new-transport (Autodesk Fusion 360 design; units mm, degrees)
Autodesk Fusion 360 part; units mm, degrees
sketch "스케치1" plane through (0, 0, 0) normal (0, 0, 1) x (1, 0, 0)
  line L0 (0, 0) -> (190, 0)
  line L1 (190, 0) -> (190, 190)
  line L2 (190, 190) -> (0, 190)
  line L3 (0, 190) -> (0, 0)
  dimension "d1" = 190
  dimension "d2" = 190
  constraint horizontal L0
  constraint vertical L1
  constraint horizontal L2
  constraint vertical L3
  constraint coincident L0.start L3.end
  measures "d1" distance of L0.start L0.end
  measures "d2" distance of L0.start L2.end
extrude "돌출1" add sketch "스케치1" along normal blind 3 makes body 1 in component "Component"
sketch "스케치2" plane through (0, 0, 3) normal (0, 0, 1) x (-1, 0, 0)
  line L0 (0, -190) -> (0, 0)
  line L1 (0, 0) -> (-190, 0)
  line L2 (-190, 0) -> (-190, -190)
  line L3 (-190, -190) -> (0, -190)
  line L4 (0, 0) -> (-3, 0)
  line L5 (-3, 0) -> (-3, -190)
  line L6 (-3, -190) -> (0, -190)
  line L7 (0, -190) -> (0, 0)
  line L8 (-3, -180) -> (-6, -180)
  line L9 (-6, -180) -> (-6, -170)
  line L10 (-6, -170) -> (-3, -170)
  line L11 (-3, -170) -> (-3, -180)
  line L12 (-3, -10) -> (-6, -10)
  line L13 (-6, -10) -> (-6, -20)
  line L14 (-6, -20) -> (-3, -20)
  line L15 (-3, -20) -> (-3, -10)
  dimension "d5" = 3
  dimension "d6" = 3
  dimension "d7" = 10
  dimension "d8" = 3
  dimension "d9" = 10
  dimension "d10" = 10
  dimension "d11" = 10
  constraint horizontal L4
  constraint vertical L5
  constraint horizontal L6
  constraint vertical L7
  constraint coincident L3 L5.end
  constraint coincident L0.end L1.start
  constraint horizontal L8
  constraint vertical L9
  constraint horizontal L10
  constraint vertical L11
  constraint coincident L5 L8.start
  constraint horizontal L12
  constraint vertical L13
  constraint horizontal L14
  constraint vertical L15
  constraint coincident L5 L12.start
  measures "d5" distance of L5.end L0.start
  measures "d6" distance of L8.start L8.end
  measures "d7" distance of L8.start L10.end
  measures "d8" distance of L12.start L12.end
  measures "d9" distance of L12.start L14.end
  measures "d10" distance of L1 L12
  measures "d11" distance of L3 L8
extrude "돌출1'" add sketch "스케치2" along normal blind 100 separate body contours L0 L1 L3 L4 L5 L6 L7 L11 L15 makes body 2 in component "Component'"
sketch "스케치3" plane through (3, 0, 0) normal (1, 0, 0) x (0, 1, 0)
  line L0 (0, 3) -> (190, 3)
  line L1 (190, 3) -> (190, 103)
  line L2 (190, 103) -> (0, 103)
  line L3 (0, 103) -> (0, 3)
  line L4 (30, 3) -> (160, 3)
  line L5 (160, 3) -> (160, 53)
  line L6 (160, 53) -> (30, 53)
  line L7 (30, 53) -> (30, 3)
  dimension "d14" = 130
  dimension "d15" = 50
  dimension "d16" = 30
  constraint horizontal L4
  constraint vertical L5
  constraint horizontal L6
  constraint vertical L7
  constraint coincident L0 L4.start
  measures "d14" distance of L4.start L4.end
  measures "d15" distance of L4.start L6.end
  measures "d16" distance of L3 L7
extrude "돌출2" cut sketch "스케치3" against normal blind 3 contours L0 L4 L5 L6 L7 bodies 2 in component "Component'"
extrude "돌출1''" add sketch "스케치2" along normal blind 10 separate body contours L5 L8 L9 L10 L11 | L5 L12 L13 L14 L15 makes body 3 at (6, 176.6667, 6.3333) makes body 4 at (3, 13.3333, 6.3333) in component "Component''"
extrude "돌출2'" cut sketch "스케치2" against normal blind 3 contours L5 L8 L9 L10 L11 | L5 L12 L13 L14 L15 bodies 1 in component "Component"
extrude "돌출2''" add sketch "스케치2" against normal blind 3 contours L5 L8 L9 L10 L11 | L5 L12 L13 L14 L15 bodies 3 4 in component "Component''"
sketch "스케치4" plane through (6, 0, 0) normal (1, 0, 0) x (0, 1, 0)
  line L0 (20, 0) -> (20, 13)
  line L1 (20, 13) -> (10, 13)
  line L2 (10, 13) -> (10, 0)
  line L3 (10, 0) -> (20, 0)
  circle A0 centre (15, 8) radius 2.05
  circle A1 centre (175, 8) radius 2.05
  line L4 (170, 0) -> (170, 13)
  line L5 (170, 13) -> (180, 13)
  dimension "d25" = 4.1
  dimension "d26" = 5
  dimension "d27" = 5
  dimension "d28" = 4.1
  dimension "d29" = 5
  dimension "d30" = 5
  measures "d25" diameter of A0
  measures "d26" distance of L1 A0.centre
  measures "d27" distance of L0 A0.centre
  measures "d28" diameter of A1
  measures "d29" distance of A1.centre L4
  measures "d30" distance of A1.centre L5
extrude "돌출3" cut sketch "스케치4" against normal blind 10 contours A0 | A1 bodies 2 in component "Component'"
extrude "돌출3'" cut sketch "스케치4" against normal blind 10 contours A0 | A1 bodies 3 4 in component "Component''"
fillet "모깎기1" radius 20 2 edges at (190, 0, 1.5) (190, 190, 1.5) on bodies 1 in component "Component"
sketch "스케치5" plane through (0, 0, 3) normal (0, 0, 1) x (-1, 0, 0)
  arc A0 (-190, -170) -> (-170, -190) centre (-170, -170) ccw
  line L0 (-170, -190) -> (0, -190)
  line L1 (0, -190) -> (0, 0)
  line L2 (0, 0) -> (-170, 0)
  arc A1 (-170, 0) -> (-190, -20) centre (-170, -20) ccw
  line L3 (-190, -20) -> (-190, -170)
  line L4 (-6, -10) -> (-3, -10)
  line L5 (-3, -10) -> (-3, -20)
  line L6 (-3, -20) -> (-6, -20)
  line L7 (-6, -20) -> (-6, -10)
  line L8 (-6, -180) -> (-6, -170)
  line L9 (-6, -170) -> (-3, -170)
  line L10 (-3, -170) -> (-3, -180)
  line L11 (-3, -180) -> (-6, -180)
  line L12 (0, 0) -> (-20, 0)
  line L13 (-20, 0) -> (-20, -30)
  line L14 (-20, -30) -> (0, -30)
  line L15 (0, -30) -> (0, 0)
  line L16 (0, -190) -> (-20, -190)
  line L17 (-20, -190) -> (-20, -160)
  line L18 (-20, -160) -> (0, -160)
  line L19 (0, -160) -> (0, -190)
  line L20 (-20, -160) -> (0, -160)
  line L21 (0, -160) -> (0, -30)
  line L22 (0, -30) -> (-20, -30)
  line L23 (-20, -30) -> (-20, -160)
  line L24 (-20, -110) -> (-140, -110)
  line L25 (-140, -110) -> (-140, -80)
  line L26 (-140, -80) -> (-20, -80)
  line L27 (-20, -80) -> (-20, -110)
  line L28 (-140, -110) -> (-20, -110)
  line L29 (-20, -110) -> (-20, -190)
  line L30 (-20, -190) -> (-140, -190)
  line L31 (-140, -190) -> (-140, -110)
  line L32 (-140, -80) -> (-20, -80)
  line L33 (-20, -80) -> (-20, 0)
  line L34 (-20, 0) -> (-140, 0)
  line L35 (-140, 0) -> (-140, -80)
  dimension "d37" = 20
  dimension "d38" = 30
  dimension "d39" = 20
  dimension "d40" = 30
  dimension "d41" = 120
  dimension "d42" = 30
  constraint horizontal L12
  constraint vertical L13
  constraint horizontal L14
  constraint vertical L15
  constraint coincident L1.end L2.start
  constraint horizontal L16
  constraint vertical L17
  constraint horizontal L18
  constraint vertical L19
  constraint coincident L0.end L1.start
  constraint horizontal L20
  constraint vertical L21
  constraint horizontal L22
  constraint vertical L23
  constraint horizontal L24
  constraint vertical L25
  constraint horizontal L26
  constraint vertical L27
  constraint coincident L23 L24.start
  constraint horizontal L28
  constraint vertical L29
  constraint horizontal L30
  constraint vertical L31
  constraint horizontal L32
  constraint vertical L33
  constraint horizontal L34
  constraint vertical L35
  measures "d37" distance of L1.end L12.end
  measures "d38" distance of L1.end L14.end
  measures "d39" distance of L0.end L16.end
  measures "d40" distance of L0.end L18.end
  measures "d41" distance of L24.start L24.end
  measures "d42" distance of L24.start L26.end
extrude "돌출3''" cut sketch "스케치5" against normal blind 3 contours L0 L17 L23 L24 L28 L29 L30 L31 | L2 L13 L23 L26 L32 L33 L34 L35 bodies 1 in component "Component"
extrude "돌출4" add 2 faces at (140, 163.3333, 2) (140, 26.6667, 2) along direction (-1, 0, 0) blind 11 on bodies 1 bodies 1 in component "Component"
sketch "스케치6" plane through (0, 0, 3) normal (0, 0, 1) x (-1, 0, 0)
  line L0 (-129, 0) -> (-170, 0)
  arc A0 (-170, 0) -> (-190, -20) centre (-170, -20) ccw
  line L1 (-190, -20) -> (-190, -170)
  arc A1 (-190, -170) -> (-170, -190) centre (-170, -170) ccw
  line L2 (-170, -190) -> (-129, -190)
  line L3 (-129, -190) -> (-129, -110)
  line L4 (-129, -110) -> (-20, -110)
  line L5 (-20, -110) -> (-20, -190)
  line L6 (-20, -190) -> (0, -190)
  line L7 (0, -190) -> (0, 0)
  line L8 (0, 0) -> (-20, 0)
  line L9 (-20, 0) -> (-20, -80)
  line L10 (-20, -80) -> (-129, -80)
  line L11 (-129, -80) -> (-129, 0)
  line L12 (-6, -10) -> (-3, -10)
  line L13 (-3, -10) -> (-3, -20)
  line L14 (-3, -20) -> (-6, -20)
  line L15 (-6, -20) -> (-6, -10)
  line L16 (-6, -180) -> (-6, -170)
  line L17 (-6, -170) -> (-3, -170)
  line L18 (-3, -170) -> (-3, -180)
  line L19 (-3, -180) -> (-6, -180)
  line L20 (-129, -190) -> (-132, -190)
  line L21 (-132, -190) -> (-132, 0)
  line L22 (-132, 0) -> (-129, 0)
  line L23 (-129, 0) -> (-129, -190)
  line L24 (-132, -180) -> (-135, -180)
  line L25 (-135, -180) -> (-135, -170)
  line L26 (-135, -170) -> (-132, -170)
  line L27 (-132, -170) -> (-132, -180)
  line L28 (-132, -10) -> (-135, -10)
  line L29 (-135, -10) -> (-135, -20)
  line L30 (-135, -20) -> (-132, -20)
  line L31 (-132, -20) -> (-132, -10)
  dimension "d47" = 3
  dimension "d48" = 190
  dimension "d49" = 3
  dimension "d50" = 10
  dimension "d51" = 10
  dimension "d52" = 3
  dimension "d53" = 10
  dimension "d54" = 10
  constraint horizontal L20
  constraint vertical L21
  constraint horizontal L22
  constraint vertical L23
  constraint coincident L2.end L3.start
  constraint horizontal L24
  constraint vertical L25
  constraint horizontal L26
  constraint vertical L27
  constraint coincident L21 L24.start
  constraint horizontal L28
  constraint vertical L29
  constraint horizontal L30
  constraint vertical L31
  constraint coincident L21 L28.start
  measures "d47" distance of L2.end L20.end
  measures "d48" distance of L2.end L0.start
  measures "d49" distance of L24.start L24.end
  measures "d50" distance of L24.start L26.end
  measures "d51" distance of L2 L24
  measures "d52" distance of L28.start L28.end
  measures "d53" distance of L28.start L30.end
  measures "d54" distance of L0 L28
extrude "돌출1'''" add sketch "스케치6" along normal blind 50 separate body contours L0 L2 L3 L11 L20 L21 L22 L23 L27 L31 makes body 5 in component "Component'''"
extrude "돌출1''''" add sketch "스케치6" along normal blind 10 separate body contours L21 L28 L29 L30 L31 | L21 L24 L25 L26 L27 makes body 6 at (132, 16.6667, 6.3333) makes body 7 at (132, 176.6667, 6.3333) in component "Component''''"
extrude "돌출5" cut sketch "스케치6" against normal blind 3 contours L21 L28 L29 L30 L31 | L21 L24 L25 L26 L27 bodies 1 in component "Component"
extrude "돌출2'''" add sketch "스케치6" against normal blind 3 contours L21 L28 L29 L30 L31 | L21 L24 L25 L26 L27 bodies 6 7 in component "Component''''"
sketch "스케치7" plane through (135, 0, 0) normal (1, 0, 0) x (0, 1, 0)
  line L0 (20, 0) -> (20, 13)
  line L1 (20, 13) -> (10, 13)
  line L2 (10, 13) -> (10, 0)
  line L3 (10, 0) -> (20, 0)
  circle A0 centre (15, 8) radius 2.05
  circle A1 centre (175, 8) radius 2.05
  line L4 (170, 0) -> (170, 13)
  line L5 (170, 13) -> (180, 13)
  dimension "d63" = 4.1
  dimension "d64" = 5
  dimension "d65" = 4.1
  dimension "d66" = 5
  dimension "d67" = 5
  measures "d63" diameter of A0
  measures "d64" distance of L1 A0.centre
  measures "d65" diameter of A1
  measures "d66" distance of A1.centre L4
  measures "d67" distance of A1.centre L5
extrude "돌출2''''" cut sketch "스케치7" against normal blind 6 contours A0 | A1 bodies 5 in component "Component'''"
extrude "돌출3'''" cut sketch "스케치7" against normal blind 6 contours A0 | A1 bodies 6 7 in component "Component''''"
extrude "돌출4'" add 1 faces at (2, 116.6667, 53) along direction (0, 0, -1) blind 50 on bodies 2 bodies 2 in component "Component'"
sketch "스케치8" plane through (0, 0, 0) normal (0, 0, 1) x (1, 0, 0)
  line L0 (0, -30) -> (125, -30)
  line L1 (125, -30) -> (125, -125)
  line L2 (125, -125) -> (0, -125)
  line L3 (0, -125) -> (0, -30)
  dimension "d74" = 125
  dimension "d75" = 95
  constraint horizontal L0
  constraint vertical L1
  constraint horizontal L2
  constraint vertical L3
  measures "d74" distance of L0.start L0.end
  measures "d75" distance of L0.start L2.end
extrude "돌출1'''''" add sketch "스케치8" along normal blind 3 separate body makes body 8
sketch "스케치9" plane through (0, 0, 3) normal (0, 0, 1) x (-1, 0, 0)
  line L0 (0, 125) -> (-125, 125)
  line L1 (-125, 125) -> (-125, 30)
  line L2 (-125, 30) -> (0, 30)
  line L3 (0, 30) -> (0, 125)
  line L4 (-3, 30) -> (-6, 30)
  line L5 (-6, 30) -> (-6, 40)
  line L6 (-6, 40) -> (-3, 40)
  line L7 (-3, 40) -> (-3, 30)
  line L8 (-3, 40) -> (-6, 40)
  line L9 (-6, 40) -> (-6, 45)
  line L10 (-6, 45) -> (-3, 45)
  line L11 (-3, 45) -> (-3, 40)
  line L12 (-3, 40) -> (-6, 40)
  line L13 (-6, 40) -> (-6, 35)
  line L14 (-6, 35) -> (-3, 35)
  line L15 (-3, 35) -> (-3, 40)
  line L16 (-119, 30) -> (-122, 30)
  line L17 (-122, 30) -> (-122, 35)
  line L18 (-122, 35) -> (-119, 35)
  line L19 (-119, 35) -> (-119, 30)
  line L20 (-119, 35) -> (-122, 35)
  line L21 (-122, 35) -> (-122, 45)
  line L22 (-122, 45) -> (-119, 45)
  line L23 (-119, 45) -> (-119, 35)
  dimension "d78" = 3
  dimension "d79" = 10
  dimension "d80" = 3
  dimension "d81" = 5
  dimension "d82" = 3
  dimension "d83" = 5
  dimension "d84" = 3
  dimension "d85" = 5
  dimension "d86" = 10
  dimension "d87" = 3
  constraint horizontal L4
  constraint vertical L5
  constraint horizontal L6
  constraint vertical L7
  constraint coincident L2 L4.start
  constraint horizontal L8
  constraint vertical L9
  constraint horizontal L10
  constraint vertical L11
  constraint horizontal L12
  constraint vertical L13
  constraint horizontal L14
  constraint vertical L15
  constraint horizontal L16
  constraint vertical L17
  constraint horizontal L18
  constraint vertical L19
  constraint coincident L2 L16.start
  constraint horizontal L20
  constraint vertical L21
  constraint horizontal L22
  constraint vertical L23
  measures "d78" distance of L4.start L4.end
  measures "d79" distance of L4.start L6.end
  measures "d80" distance of L6.end L5.end
  measures "d81" distance of L6.end L10.end
  measures "d82" distance of L3 L7
  measures "d83" distance of L6.end L14.end
  measures "d84" distance of L16.start L16.end
  measures "d85" distance of L16.start L18.end
  measures "d86" distance of L18.end L22.end
  measures "d87" distance of L1 L17
extrude "돌출2'''''" cut sketch "스케치9" against normal blind 3 contours L5 L6 L7 L8 L12 L13 L14 L15 | L18 L20 L21 L22 L23 | L6 L8 L9 L10 L11 L12 bodies 8
extrude "돌출1''''''" add sketch "스케치9" along normal blind 10 separate body contours L2 L4 L5 L7 L14 | L2 L16 L17 L18 L19 L20 | L5 L6 L7 L8 L12 L13 L14 L15 | L18 L20 L21 L22 L23 | L6 L8 L9 L10 L11 L12 makes body 9 at (3, -40, 6.3333) makes body 10 at (119, -40, 6.3333) in component "Component'''''"
copy_body "본체->구성요소1" bodies 8 removing the originals makes body 11 in component "Component''''''"
extrude "돌출2''''''" add sketch "스케치9" against normal blind 3 contours L5 L6 L7 L8 L12 L13 L14 L15 | L18 L20 L21 L22 L23 | L6 L8 L9 L10 L11 L12 bodies 9 10 in component "Component'''''"
sketch "스케치10" plane through (122, 0, 0) normal (1, 0, 0) x (0, 1, 0)
  line L0 (-35, 3) -> (-30, 3)
  line L1 (-30, 3) -> (-30, 13)
  line L2 (-30, 13) -> (-45, 13)
  line L3 (-45, 13) -> (-45, 0)
  line L4 (-45, 0) -> (-35, 0)
  line L5 (-35, 0) -> (-35, 3)
  circle A0 centre (-40, 8) radius 2.05
  dimension "d94" = 4.1
  dimension "d95" = 5
  dimension "d96" = 5
  measures "d94" diameter of A0
  measures "d95" distance of L2 A0.centre
  measures "d96" distance of L3 A0.centre
extrude "돌출3''''" cut sketch "스케치10" against normal blind 200 contours A0 bodies 9 10 in component "Component'''''"
sketch "스케치11" plane through (132, 0, 0) normal (1, 0, 0) x (0, 1, 0)
  circle A0 centre (15, 8) radius 2.05
  circle A1 centre (175, 8) radius 2.05
  line L0 (0, 3) -> (190, 3)
  line L1 (190, 3) -> (190, 53)
  line L2 (190, 53) -> (0, 53)
  line L3 (0, 53) -> (0, 3)
  circle A2 centre (105, 45) radius 2.05
  line L4 (95, 53) -> (95, 3)
  circle A3 centre (85, 45) radius 2.05
  dimension "d101" = 4.1
  dimension "d102" = 10
  dimension "d103" = 8
  constraint midpoint L2 L4.start
  constraint midpoint L0 L4.end
  constraint symmetric A2 L4 A3
  measures "d101" diameter of A2
  measures "d102" distance of A2.centre L4
  measures "d103" distance of L2 A2.centre
fillet "모깎기1'" radius 5 2 edges at (4.5, -30, 13) (120.5, -30, 13) on bodies 9 10 in component "Component'''''"
extrude "돌출3'''''" cut sketch "스케치11" against normal blind 3 contours A2 | A3 bodies 5 in component "Component'''"
extrude "돌출1'''''''" cut 1 faces at (83.3333, -125, 1) along direction (0, 1, 0) blind 5 on bodies 11 bodies 11 in component "Component''''''"
extrude "돌출4''" add sketch "스케치9" along normal blind 10 contours L2 L4 L5 L7 L14 | L2 L16 L17 L18 L19 L20 bodies 9 10 in component "Component'''''"
fillet "모깎기2" radius 5 2 edges at (4.5, -45, 13) (120.5, -45, 13) on bodies 9 10 in component "Component'''''"
extrude "돌출5'" cut sketch "스케치9" along normal blind 5 from surface at 5 contours L2 L4 L5 L7 L14 | L2 L16 L17 L18 L19 L20 bodies 9 10 in component "Component'''''"
fillet "모깎기3" radius 5 2 edges at (4.5, -35, 13) (120.5, -35, 13) on bodies 9 10 in component "Component'''''"
fillet "모깎기4" radius 5 2 edges at (4.5, -30, 8) (120.5, -30, 8) on bodies 9 10 in component "Component'''''"
component "Component" placed x (1, 0, 0) y (0, 1, 0) z (0, 0, 1) at (0, 0, 0)
component "Component'" placed x (1, 0, 0) y (0, 1, 0) z (0, 0, 1) at (0, 0, 0)
component "Component''" placed x (1, 0, 0) y (0, 1, 0) z (0, 0, 1) at (0, 0, 0)
component "Component'''" placed x (1, 0, 0) y (0, 1, 0) z (0, 0, 1) at (0, 0, 0)
component "Component''''" placed x (1, 0, 0) y (0, 1, 0) z (0, 0, 1) at (0, 0, 0)
component "Component'''''" placed x (1, 0, 0) y (0, 1, 0) z (0, 0, 1) at (0, 0, 0)
component "Component''''''" placed x (1, 0, 0) y (0, 1, 0) z (0, 0, 1) at (0, 0, 0)
